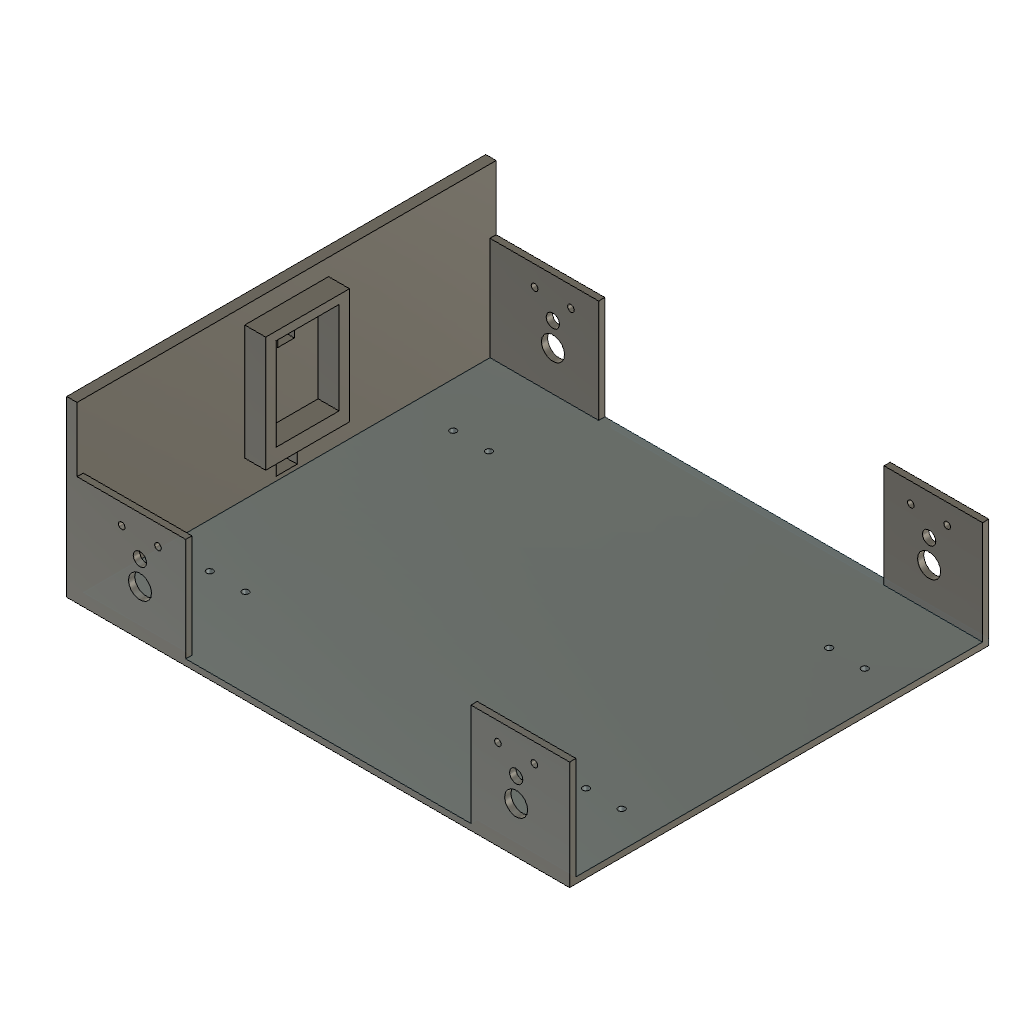
MAIN CHASSIS (Autodesk Fusion 360 design; units mm, degrees)
part number: 2026-11-04-09-08-16-697
Autodesk Fusion 360 part; units mm, degrees
derive "DerivedContext1"
sketch "Sketch1" plane through (0, 0, 0) normal (0, 0, 1) x (1, 0, 0)
  line L0 (90, 130) -> (-90, 130)
  line L1 (-90, 130) -> (-90, -130)
  line L2 (-90, -130) -> (90, -130)
  line L3 (90, -130) -> (90, 130)
  line L4 (90, 130) -> (-90, -130) construction
  line L5 (-90, 130) -> (90, -130) construction
  dimension "d1" = 260
  dimension "d2" = 180
  constraint horizontal L0
  constraint perpendicular L0 L1
  constraint parallel L0 L2
  constraint parallel L1 L3
  constraint coincident L4 origin
  constraint coincident L5 origin
  measures "d1" distance of L0.end L1.end
  measures "d2" distance of L1.end L2.end
extrude "Extrude1" add sketch "Sketch1" along normal blind 3 makes body 1
sketch "Sketch2" plane through (0, 130, 0) normal (0, 1, 0) x (-1, 0, 0)
  line L0 (90, 0) -> (90, 3)
  line L1 (-90, 3) -> (-90, 0)
  line L2 (-90, 0) -> (-90, 3)
  line L3 (90, -0.0888) -> (90, 0)
  constraint vertical L2
  constraint vertical L3
  constraint coincident L1.start L2.end
  constraint coincident L0.start L3.end
sketch "Sketch3" plane through (0, 130, 0) normal (0, 1, 0) x (-1, 0, 0)
  line L0 (250, -50) -> (30, -50)
  line L1 (30, -50) -> (30, -47)
  line L2 (30, -47) -> (250, -47)
  line L3 (250, -47) -> (250, -50)
  dimension "d5" = 220
  dimension "d6" = 3
  constraint horizontal L0
  constraint vertical L1
  constraint horizontal L2
  constraint vertical L3
  measures "d5" distance of L1.end L2.end
  measures "d6" distance of L0.end L1.end
extrude "Extrude2" add sketch "Sketch3" along normal blind 20 separate body makes body 2
combine "Combine1" operation add target body 1 tool bodies 2 makes body 3 at (-176.6667, 136.6667, -50)
move_body "Move1" bodies 3 to x (1, 0, 0) y (0, 1, 0) z (0, 0, 1) at (161.0055, -0.0826, 50.4305)
extrude "Extrude3" cut 1 faces at (131.0055, 136.5841, 1.4305) along direction (-1, 0, 0) blind 40 on bodies 3 bodies 3
extrude "Extrude4" add 1 faces at (-88.9945, 136.5841, 2.4305) along direction (-1, 0, 0) blind 20 on bodies 3 bodies 1 3
extrude "Extrude5" add 1 faces at (91.0055, 136.5841, 1.4305) along direction (1, 0, 0) blind 20 on bodies 1 bodies 1
extrude "Extrude6" add 1 faces at (30.6703, 143.2783, 0.4305) along direction (0, 0, -1) blind 0.4 on bodies 1 bodies 1
extrude "Extrude7" cut 1 faces at (-35.6612, 136.5841, 3.4305) along direction (0, 0, -1) blind 0.4 on bodies 1 bodies 1
extrude "Extrude8" add 1 faces at (-108.9945, 136.5841, 2.0305) along direction (-1, 0, 0) blind 1 on bodies 1 bodies 1
extrude "Extrude9" cut 1 faces at (111.0055, 136.5841, 2.0305) along direction (-1, 0, 0) blind 1 on bodies 1 bodies 1
sketch "Sketch4" plane through (0, 0, 3) normal (0, 0, 1) x (-1, 0, 0)
  line L0 (-90, -129.9174) -> (90, -129.9174)
  line L1 (90, -129.9174) -> (90, 130)
  line L2 (90, 130) -> (-90, 130)
  line L3 (-90, 130) -> (-90, -129.9174)
  line L4 (110, 130) -> (-110, 130)
  line L5 (-110, 130) -> (-110, 150)
  line L6 (-110, 150) -> (110, 150)
  line L7 (110, 150) -> (110, 130)
  constraint horizontal L4
  constraint vertical L5
  constraint horizontal L6
  constraint vertical L7
extrude "Extrude10" add sketch "Sketch4" along normal blind 3 separate body contours L2 L4 L5 L6 L7 makes body 4
extrude "Extrude11" add 1 faces at (30, -143.3333, 3) along direction (0, 0, -1) blind 3 on bodies 4 bodies 1 4
extrude "Extrude12" cut 1 faces at (36.6667, -143.3333, 6) along direction (0, 0, -1) blind 3 on bodies 1 bodies 1
extrude "Extrude13" add 1 faces at (30.0037, 143.2783, 0.0305) along direction (0, 0, -1) blind 0.031 on bodies 1 bodies 1
sketch "Sketch5" plane through (0, 0, 3) normal (0, 0, 1) x (-1, 0, 0)
  line L0 (-110, 150) -> (-110, 130)
  line L1 (-110, 130) -> (-90, 130)
  line L2 (-90, 130) -> (-90, -129.9174)
  line L3 (-90, -129.9174) -> (90, -129.9174)
  line L4 (90, -129.9174) -> (90, 130)
  line L5 (110, 130) -> (110, 150)
  line L6 (110, 150) -> (-110, 150)
  line L7 (90, 130) -> (110, 130)
extrude "Extrude14" add 1 faces at (110.0055, 143.2507, 1.0099) along direction (1, 0, 0) blind 20 on bodies 1 bodies 1
sketch "Sketch6" plane through (130.0055, 0, 0) normal (1, 0, 0) x (0, 1, 0)
  line L0 (149.9174, 3.0305) -> (129.9174, 3.0305)
  line L1 (129.9174, 3.0305) -> (129.9174, -0.0005)
  line L2 (129.9174, -0.0005) -> (149.9174, -0.0005)
  line L3 (149.9174, -0.0005) -> (149.9174, 3.0305)
sketch "Sketch7" plane through (0, 129.9174, 0) normal (0, -1, 0) x (1, 0, 0)
  line L0 (130.0055, 3.0305) -> (-109.9945, 3.0305)
  line L1 (-109.9945, 3.0305) -> (-109.9945, -0.0005)
  line L2 (-109.9945, -0.0005) -> (-90, -0.0005)
  line L3 (-90, -0.0005) -> (-90, 0)
  line L4 (-90, 0) -> (-90, 3)
  line L5 (-90, 3) -> (90, 3)
  line L6 (90, 3) -> (90, 0)
  line L7 (90, 0) -> (90, -0.0005)
  line L8 (90, -0.0005) -> (130.0055, -0.0005)
  line L9 (130.0055, -0.0005) -> (130.0055, 3.0305)
extrude "Extrude15" add sketch "Sketch6" along normal blind 20 bodies 1
extrude "Extrude16" add 1 faces at (-23.3278, 149.9174, 2.0202) along direction (0, 1, 0) blind 20 on bodies 1 bodies 1
extrude "Extrude17" add 1 faces at (-109.9945, 156.5841, 1.0099) along direction (-1, 0, 0) blind 40 on bodies 1 bodies 1
extrude "Extrude18" add 1 faces at (36.6667, -150, 1) along direction (0, -1, 0) blind 20 on bodies 1 bodies 1
extrude "Extrude19" add 1 faces at (-110, -156.6667, 1) along direction (-1, 0, 0) blind 40 on bodies 1 bodies 1
extrude "Extrude20" add 1 faces at (110, -156.6667, 1) along direction (1, 0, 0) blind 40 on bodies 1 bodies 1
sketch "Sketch8" plane through (0, 0, 3) normal (0, 0, 1) x (-1, 0, 0)
  line L0 (-90, -129.9174) -> (90, -129.9174)
  line L1 (90, -129.9174) -> (90, 130)
  line L2 (90, 130) -> (150, 130)
  line L3 (150, 130) -> (150, 170)
  line L4 (150, 170) -> (-150, 170)
  line L5 (-150, 170) -> (-150, 130)
  line L6 (-150, 130) -> (-90, 130)
  line L7 (-90, 130) -> (-90, -129.9174)
extrude "Extrude21" cut 1 faces at (90, -43.3609, 1) along direction (-1, 0, 0) blind 10 on bodies 1 bodies 1
extrude "Extrude22" cut 1 faces at (150.0055, 143.2507, 1.0099) along direction (-1, 0, 0) blind 10 on bodies 1 bodies 1
extrude "Extrude23" cut 1 faces at (-90, 43.2783, 1) along direction (1, 0, 0) blind 10 on bodies 1 bodies 1
extrude "Extrude24" cut 1 faces at (-149.9945, 156.5841, 1.0099) along direction (1, 0, 0) blind 10 on bodies 1 bodies 1
extrude "Extrude25" cut 1 faces at (-150, -156.6667, 1) along direction (1, 0, 0) blind 10 on bodies 1 bodies 1
extrude "Extrude26" cut 1 faces at (150, -156.6667, 1) along direction (-1, 0, 0) blind 10 on bodies 1 bodies 1
extrude "Extrude27" add 2 faces at (-120, -130, 1) (100, -130, 2) along direction (0, 1, 0) blind 20 on bodies 1 bodies 1
extrude "Extrude28" cut 1 faces at (46.6667, -170, 2) along direction (0, 1, 0) blind 20 on bodies 1 bodies 1
sketch "Sketch9" plane through (0, 0, 3) normal (0, 0, 1) x (-1, 0, 0)
  line L0 (140, 150) -> (-140, 150)
  line L1 (-140, 150) -> (-140, 110)
  line L2 (-140, 110) -> (-80, 110)
  line L3 (-80, 110) -> (-80, -129.9174)
  line L4 (-80, -129.9174) -> (80, -129.9174)
  line L5 (80, -129.9174) -> (80, 110)
  line L6 (80, 110) -> (140, 110)
  line L7 (140, 110) -> (140, 150)
extrude "Extrude29" add 2 faces at (-120, -110, 1) (100, -110, 2) along direction (0, 1, 0) blind 80 on bodies 1 bodies 1
extrude "Extrude30" cut 1 faces at (46.6667, -150, 2) along direction (0, 1, 0) blind 80 on bodies 1 bodies 1
sketch "Sketch10" plane through (0, 0, 3) normal (0, 0, 1) x (-1, 0, 0)
  line L0 (140, 70) -> (-140, 70)
  line L1 (-140, 70) -> (-140, 30)
  line L2 (-140, 30) -> (-80, 30)
  line L3 (-80, 30) -> (-80, -129.9174)
  line L4 (-80, -129.9174) -> (80, -129.9174)
  line L5 (80, -129.9174) -> (80, 30)
  line L6 (80, 30) -> (140, 30)
  line L7 (140, 30) -> (140, 70)
extrude "Extrude31" add 2 faces at (-120, -30, 1) (100, -30, 2) along direction (0, 1, 0) blind 40 on bodies 1 bodies 1
extrude "Extrude32" cut 1 faces at (46.6667, -70, 2) along direction (0, 1, 0) blind 40 on bodies 1 bodies 1
extrude "Extrude33" cut 1 faces at (-139.9945, 156.5841, 1.0099) along direction (1, 0, 0) blind 20 on bodies 1 bodies 1
extrude "Extrude34" cut 1 faces at (-80, 89.9449, 1) along direction (1, 0, 0) blind 20 on bodies 1 bodies 1
extrude "Extrude35" cut 1 faces at (-140, -3.3333, 2) along direction (1, 0, 0) blind 20 on bodies 1 bodies 1
extrude "Extrude36" cut 1 faces at (140.0055, 143.2507, 1.0099) along direction (-1, 0, 0) blind 20 on bodies 1 bodies 1
extrude "Extrude37" cut 1 faces at (140, -3.3333, 2) along direction (-1, 0, 0) blind 20 on bodies 1 bodies 1
extrude "Extrude38" cut 1 faces at (80, 49.9725, 1) along direction (-1, 0, 0) blind 20 on bodies 1 bodies 1
extrude "Extrude39" add 1 faces at (-89.9982, 129.9174, 2.0102) along direction (0, -1, 0) blind 10 on bodies 1 bodies 1
extrude "Extrude40" add 1 faces at (80, 10, 2) along direction (0, 1, 0) blind 10 on bodies 1 bodies 1
extrude "Extrude41" add 1 faces at (-100, 10, 1) along direction (0, 1, 0) blind 10 on bodies 1 bodies 1
extrude "Extrude42" add 2 faces at (-100, 20, 1) (80, 20, 2) along direction (0, 1, 0) blind 20 on bodies 1 bodies 1
extrude "Extrude43" add 1 faces at (-89.9982, 119.9174, 2.0102) along direction (0, -1, 0) blind 20 on bodies 1 bodies 1
extrude "Extrude44" cut 1 faces at (40.0055, 123.2507, 3.0305) along direction (0, 0, -1) blind 10 on bodies 1 bodies 1
extrude "Extrude45" add 1 faces at (-20, 99.9174, 2) along direction (0, 1, 0) blind 70 on bodies 1 bodies 1
extrude "Extrude46" add 1 faces at (60, 126.6116, 1) along direction (1, 0, 0) blind 60 on bodies 1 bodies 1
extrude "Extrude47" add 1 faces at (-100, 40, 1) along direction (0, 1, 0) blind 130 on bodies 1 bodies 1
sketch "Sketch11" plane through (0, 0, 3) normal (0, 0, 1) x (-1, 0, 0)
  line L0 (60, -169.9174) -> (60, -170)
  line L1 (60, -170) -> (120, -170)
  line L2 (120, -170) -> (120, 30)
  line L3 (120, 30) -> (-120, 30)
  line L4 (-120, 30) -> (-120, -169.9174)
  line L5 (-120, -169.9174) -> (60, -169.9174)
  line L6 (120, 30) -> (105, 30)
  line L7 (105, 30) -> (105, -170)
  line L8 (105, -170) -> (120, -170)
  line L9 (120, -170) -> (120, 30)
  dimension "d105" = 15
  constraint horizontal L6
  constraint vertical L7
  constraint horizontal L8
  constraint vertical L9
  constraint coincident L1 L7.end
  constraint coincident L2.end L3.start
  measures "d105" distance of L7.end L1.end
extrude "Extrude48" add sketch "Sketch11" along normal blind 70 contours L1 L2 L3 L6 L7 L8 L9 bodies 1
extrude "Extrude49" add 1 faces at (-110, 36.6667, 73) along direction (0, 0, 1) blind 10 on bodies 1 bodies 1
sketch "Sketch12" plane through (-105, 0, 0) normal (1, 0, 0) x (0, 1, 0)
  line L0 (-30, 3) -> (170, 3)
  line L1 (170, 3) -> (170, 83)
  line L2 (170, 83) -> (-30, 83)
  line L3 (-30, 83) -> (-30, 3)
  line L4 (55, 75) -> (85, 75)
  line L5 (85, 75) -> (85, 31)
  line L6 (85, 31) -> (55, 31)
  line L7 (55, 31) -> (55, 75)
  dimension "d110" = 30
  dimension "d111" = 44
  constraint horizontal L4
  constraint vertical L5
  constraint horizontal L6
  constraint vertical L7
  measures "d110" distance of L4.start L4.end
  measures "d111" distance of L4.start L6.end
extrude "Extrude50" cut sketch "Sketch12" against normal blind 10 contours L4 L5 L6 L7 bodies 1
sketch "Sketch13" plane through (-115, 0, 0) normal (1, 0, 0) x (0, 1, 0)
  line L0 (55, 31) -> (85, 31)
  line L1 (85, 31) -> (85, 75)
  line L2 (85, 75) -> (55, 75)
  line L3 (55, 75) -> (55, 31)
  line L4 (65.7, 65.8) -> (73.7, 65.8)
  line L5 (73.7, 65.8) -> (73.7, 57.8)
  line L6 (73.7, 57.8) -> (65.7, 57.8)
  line L7 (65.7, 57.8) -> (65.7, 65.8)
  dimension "d116" = 8
  dimension "d117" = 8
  constraint horizontal L4
  constraint vertical L5
  constraint horizontal L6
  constraint vertical L7
  measures "d116" distance of L5.end L6.end
  measures "d117" distance of L4.end L5.end
extrude "Extrude51" cut sketch "Sketch13" against normal blind 5 contours L4 L5 L6 L7 bodies 1
extrude "Extrude52" cut 1 faces at (-108.3333, 75, 31) along direction (0, 0, -1) blind 4 on bodies 1 bodies 1
extrude "Extrude53" add 1 faces at (-108.3333, 65, 75) along direction (0, 0, -1) blind 4 on bodies 1 bodies 1
sketch "sketch 4915" plane through (-105, 0, 0) normal (1, 0, 0) x (0, 1, 0)
  line L0 (55, 27) -> (55, 71)
  line L1 (55, 71) -> (85, 71)
  line L2 (85, 71) -> (85, 27)
  line L3 (85, 27) -> (55, 27)
  line L4 (-30, 83) -> (50, 83)
  line L5 (50, 83) -> (50, 3)
  line L6 (50, 3) -> (-30, 3)
  line L7 (-30, 3) -> (-30, 83)
  line L8 (90, 83) -> (170, 83)
  line L9 (170, 83) -> (170, 3)
  line L10 (170, 3) -> (90, 3)
  line L11 (90, 3) -> (90, 83)
  line L12 (50, 83) -> (90, 83)
  line L13 (90, 83) -> (90, 75)
  line L14 (90, 75) -> (50, 75)
  line L15 (50, 75) -> (50, 83)
  line L16 (50, 20) -> (90, 20)
  line L17 (90, 20) -> (90, 3)
  line L18 (90, 3) -> (50, 3)
  line L19 (50, 3) -> (50, 20)
  line L20 (50, 75) -> (50, 20)
  line L21 (50, 20) -> (90, 20)
  line L22 (90, 20) -> (90, 75)
  line L23 (90, 75) -> (50, 75)
extrude "Extrude54" cut sketch "sketch 4915" against normal blind 10 contours L4 L5 L6 L7 L15 L19 L20 | L5 L11 L12 L13 L14 L15 L23 | L8 L9 L10 L11 L13 L17 L22 | L5 L11 L16 L17 L18 L19 L21 bodies 1
sketch "Sketch14" plane through (-115, 0, 0) normal (1, 0, 0) x (0, 1, 0)
  line L0 (90, 20) -> (50, 20)
  line L1 (50, 20) -> (50, 75)
  line L2 (50, 75) -> (90, 75)
  line L3 (90, 75) -> (90, 20)
  line L4 (-30, 3) -> (170, 3)
  line L5 (170, 3) -> (170, 83)
  line L6 (170, 83) -> (-30, 83)
  line L7 (-30, 83) -> (-30, 3)
  line L8 (-30, 83) -> (-27, 83)
  line L9 (-27, 83) -> (-27, 3)
  line L10 (-27, 3) -> (-30, 3)
  line L11 (-30, 3) -> (-30, 83)
  dimension "d126" = 3
  constraint horizontal L8
  constraint vertical L9
  constraint horizontal L10
  constraint vertical L11
  constraint coincident L6.end L7.start
  measures "d126" distance of L6.end L8.end
extrude "Extrude55" add sketch "Sketch14" along normal blind 235 contours L4 L6 L7 L8 L9 L10 L11 bodies 1
sketch "Sketch15" plane through (-115, 0, 0) normal (1, 0, 0) x (0, 1, 0)
  line L0 (-27, 83) -> (-27, 3)
  line L1 (-27, 3) -> (170, 3)
  line L2 (170, 3) -> (170, 83)
  line L3 (170, 83) -> (-27, 83)
  line L4 (90, 20) -> (50, 20)
  line L5 (50, 20) -> (50, 75)
  line L6 (50, 75) -> (90, 75)
  line L7 (90, 75) -> (90, 20)
  line L8 (170, 83) -> (167, 83)
  line L9 (167, 83) -> (167, 3)
  line L10 (167, 3) -> (170, 3)
  line L11 (170, 3) -> (170, 83)
  dimension "d129" = 3
  constraint horizontal L8
  constraint vertical L9
  constraint horizontal L10
  constraint vertical L11
  constraint coincident L2.end L3.start
  measures "d129" distance of L2.end L8.end
extrude "Extrude56" add sketch "Sketch15" along normal blind 235 contours L1 L2 L3 L8 L9 L10 L11 bodies 1
sketch "Sketch16" plane through (0, 169.9174, 0) normal (0, 1, 0) x (-1, 0, 0)
  line L0 (-120, 0) -> (60, 0)
  line L1 (60, 0) -> (60, 3)
  line L2 (60, 3) -> (-120, 3)
  line L3 (-120, 3) -> (-120, 0)
sketch "Sketch17" plane through (0, -27, 0) normal (0, 1, 0) x (-1, 0, 0)
  line L0 (115, 3) -> (115, 83)
  line L1 (115, 83) -> (-120, 83)
  line L2 (-120, 83) -> (-120, 3)
  line L3 (-120, 3) -> (115, 3)
  line L4 (-120, 83) -> (-117, 83)
  line L5 (-117, 83) -> (-117, 3)
  line L6 (-117, 3) -> (-120, 3)
  line L7 (-120, 3) -> (-120, 83)
  dimension "d132" = 3
  constraint horizontal L4
  constraint vertical L5
  constraint horizontal L6
  constraint vertical L7
  constraint coincident L1.end L2.start
  measures "d132" distance of L1.end L4.end
extrude "Extrude57" add sketch "Sketch17" along normal blind 194 contours L1 L2 L3 L4 L5 L6 L7 bodies 1
sketch "Sketch18" plane through (-120, 0, 0) normal (-1, 0, 0) x (0, -1, 0)
  line L0 (-73.7, 57.8) -> (-73.7, 65.8)
  line L1 (-73.7, 65.8) -> (-65.7, 65.8)
  line L2 (-65.7, 65.8) -> (-65.7, 57.8)
  line L3 (-65.7, 57.8) -> (-73.7, 57.8)
  line L4 (30, 0) -> (30, 83)
  line L5 (30, 83) -> (-170, 83)
  line L6 (-170, 83) -> (-170, 0)
  line L7 (-170, 0) -> (30, 0)
  line L8 (-92, 50) -> (-47, 50)
  line L9 (-47, 50) -> (-47, 24)
  line L10 (-47, 24) -> (-92, 24)
  line L11 (-92, 24) -> (-92, 50)
  dimension "d135" = 45
  dimension "d136" = 26
  constraint horizontal L8
  constraint vertical L9
  constraint horizontal L10
  constraint vertical L11
  measures "d135" distance of L8.start L8.end
  measures "d136" distance of L8.start L10.end
extrude "Extrude58" add sketch "Sketch18" along normal blind 15 contours L8 L9 L10 L11 bodies 1
sketch "Sketch19" plane through (-135, 0, 0) normal (-1, 0, 0) x (0, -1, 0)
  line L0 (-92, 24) -> (-47, 24)
  line L1 (-47, 24) -> (-47, 50)
  line L2 (-47, 50) -> (-92, 50)
  line L3 (-92, 50) -> (-92, 24)
  line L4 (-91, 49) -> (-48, 49)
  line L5 (-48, 49) -> (-48, 25)
  line L6 (-48, 25) -> (-91, 25)
  line L7 (-91, 25) -> (-91, 49)
  constraint horizontal L4
  constraint vertical L5
  constraint horizontal L6
  constraint vertical L7
extrude "Extrude59" cut sketch "Sketch19" against normal blind 14 contours L4 L5 L6 L7 bodies 1
extrude "Extrude60" add 1 faces at (-130, 77, 50) along direction (0, 0, 1) blind 1 on bodies 1 bodies 1
extrude "Extrude61" add 1 faces at (-125, 47, 33) along direction (0, -1, 0) blind 1 on bodies 1 bodies 1
extrude "Extrude62" add 1 faces at (-125, 92, 33) along direction (0, 1, 0) blind 1 on bodies 1 bodies 1
extrude "Extrude63" add 1 faces at (-125, 77.3333, 24) along direction (0, 0, -1) blind 1 on bodies 1 bodies 1
sketch "Sketch20" plane through (0, 91, 0) normal (0, -1, 0) x (1, 0, 0)
  line L0 (-135, 49) -> (-135, 25)
  line L1 (-135, 25) -> (-121, 25)
  line L2 (-121, 25) -> (-121, 49)
  line L3 (-121, 49) -> (-135, 49)
extrude "Extrude64" add 1 faces at (-125, 93, 41.6667) along direction (0, 1, 0) blind 2 on bodies 1 bodies 1
extrude "Extrude65" cut sketch "Sketch20" against normal blind 2 bodies 1
extrude "Extrude66" add 1 faces at (-125, 46, 41.6667) along direction (0, -1, 0) blind 2 on bodies 1 bodies 1
extrude "Extrude67" cut 1 faces at (-130.3333, 48, 41) along direction (0, -1, 0) blind 2 on bodies 1 bodies 1
extrude "Extrude68" add 1 faces at (-130, 61, 23) along direction (0, 0, -1) blind 2 on bodies 1 bodies 1
extrude "Extrude69" cut 1 faces at (-130.3333, 77.3333, 25) along direction (0, 0, -1) blind 2 on bodies 1 bodies 1
sketch "Sketch21" plane through (0, 0, 21) normal (0, 0, -1) x (1, 0, 0)
  line L0 (-120, -95) -> (-120, -44)
  line L1 (-120, -44) -> (-135, -44)
  line L2 (-135, -44) -> (-135, -95)
  line L3 (-135, -95) -> (-120, -95)
  line L4 (-122.042, -59.953) -> (-132.7538, -59.953)
  line L5 (-132.7538, -59.953) -> (-132.7538, -78.5078)
  line L6 (-132.7538, -78.5078) -> (-122.042, -78.5078)
  line L7 (-122.042, -78.5078) -> (-122.042, -59.953)
  constraint horizontal L4
  constraint vertical L5
  constraint horizontal L6
  constraint vertical L7
extrude "Extrude70" cut sketch "Sketch21" against normal blind 2 contours L4 L5 L6 L7 bodies 1
sketch "Sketch22" plane through (-120, 0, 0) normal (-1, 0, 0) x (0, -1, 0)
  line L0 (-95, 21) -> (-95, 51)
  line L1 (-95, 51) -> (-44, 51)
  line L2 (-44, 51) -> (-44, 21)
  line L3 (-44, 21) -> (-95, 21)
  line L4 (-73.7, 57.8) -> (-73.7, 65.8)
  line L5 (-73.7, 65.8) -> (-65.7, 65.8)
  line L6 (-65.7, 65.8) -> (-65.7, 57.8)
  line L7 (-65.7, 57.8) -> (-73.7, 57.8)
  line L8 (30, 0) -> (30, 83)
  line L9 (30, 83) -> (-170, 83)
  line L10 (-170, 83) -> (-170, 0)
  line L11 (-170, 0) -> (30, 0)
  line L12 (-75, 5) -> (-65, 5)
  line L13 (-65, 5) -> (-65, 10)
  line L14 (-65, 10) -> (-75, 10)
  line L15 (-75, 10) -> (-75, 5)
  constraint horizontal L12
  constraint vertical L13
  constraint horizontal L14
  constraint vertical L15
extrude "Extrude71" cut sketch "Sketch22" against normal blind 5 contours L12 L13 L14 L15 bodies 1
sketch "Sketch23" plane through (0, -30, 0) normal (0, -1, 0) x (1, 0, 0)
  line L0 (120, 0) -> (120, 83)
  line L1 (120, 83) -> (-120, 83)
  line L2 (-120, 83) -> (-120, 0)
  line L3 (-120, 0) -> (120, 0)
  circle A0 centre (-84.9709, 21.9324) radius 5.5
  circle A1 centre (-85, 33.3) radius 3.15
  dimension "d166" = 11
  dimension "d168" = 6.3
  measures "d166" diameter of A0
  measures "d168" diameter of A1
extrude "Extrude72" cut sketch "Sketch23" against normal blind 3 contours A0 | A1 bodies 1
sketch "Sketch24" plane through (0, -30, 0) normal (0, -1, 0) x (1, 0, 0)
  circle A0 centre (-85, 33.3) radius 3.15
  circle A1 centre (-84.9709, 21.9324) radius 5.5
  line L0 (120, 0) -> (120, 83)
  line L1 (120, 83) -> (-120, 83)
  line L2 (-120, 83) -> (-120, 0)
  line L3 (-120, 0) -> (120, 0)
  circle A2 centre (94.4838, 22) radius 5.5
  circle A3 centre (94.4995, 33.3368) radius 3.15
  dimension "d171" = 11
  dimension "d174" = 6.3
  measures "d171" diameter of A2
  measures "d174" diameter of A3
extrude "Extrude73" cut sketch "Sketch24" against normal blind 3 contours A2 | A3 bodies 1
sketch "Sketch25" plane through (0, -30, 0) normal (0, -1, 0) x (1, 0, 0)
  circle A0 centre (94.4995, 33.3368) radius 3.15
  circle A1 centre (94.4838, 22) radius 5.5
  circle A2 centre (-85, 33.3) radius 3.15
  circle A3 centre (-84.9709, 21.9324) radius 5.5
  line L0 (120, 0) -> (120, 83)
  line L1 (120, 83) -> (-120, 83)
  line L2 (-120, 83) -> (-120, 0)
  line L3 (-120, 0) -> (120, 0)
  circle A4 centre (103.151, 42.7931) radius 1.575
  circle A5 centre (85.7765, 42.9111) radius 1.575
  line L4 (85.7765, 42.9111) -> (86.2872, 42.6287)
  dimension "d179" = 3.15
  dimension "d181" = 3.15
  constraint coincident A5.centre L4.start
  measures "d179" diameter of A4
  measures "d181" diameter of A5
extrude "Extrude74" cut sketch "Sketch25" against normal blind 3 contours A4 | A5 bodies 1
sketch "Sketch26" plane through (0, -30, 0) normal (0, -1, 0) x (1, 0, 0)
  circle A0 centre (85.7765, 42.9111) radius 1.575
  circle A1 centre (103.151, 42.7931) radius 1.575
  circle A2 centre (94.4995, 33.3368) radius 3.15
  circle A3 centre (94.4838, 22) radius 5.5
  circle A4 centre (-85, 33.3) radius 3.15
  circle A5 centre (-84.9709, 21.9324) radius 5.5
  line L0 (120, 0) -> (120, 83)
  line L1 (120, 83) -> (-120, 83)
  line L2 (-120, 83) -> (-120, 0)
  line L3 (-120, 0) -> (120, 0)
  circle A6 centre (-76.3782, 42.7246) radius 1.575
  circle A7 centre (-93.6909, 42.7533) radius 1.575
  dimension "d186" = 3.15
  dimension "d188" = 3.15
  measures "d186" diameter of A6
  measures "d188" diameter of A7
extrude "Extrude75" cut sketch "Sketch26" against normal blind 3 contours A6 | A7 bodies 1
mirror "Mirror2" about plane through (1, 70, 43) normal (0, 1, 0) of "Extrude75"
mirror "Mirror3" about plane through (1, 70, 43) normal (0, 1, 0) of "Extrude74"
mirror "Mirror4" about plane through (1, 70, 43) normal (0, 1, 0) of "Extrude73"
mirror "Mirror5" about plane through (1, 70, 43) normal (0, 1, 0) of "Extrude72"
sketch "Sketch27" plane through (0, -30, 0) normal (0, -1, 0) x (1, 0, 0)
  line L0 (120, 0) -> (120, 83)
  line L1 (120, 83) -> (-120, 83)
  line L2 (-120, 83) -> (-120, 0)
  line L3 (-120, 0) -> (120, 0)
  circle A0 centre (-84.9709, 21.9324) radius 5.5
  circle A1 centre (-85, 33.3) radius 3.15
  circle A2 centre (94.4838, 22) radius 5.5
  circle A3 centre (94.4995, 33.3368) radius 3.15
  circle A4 centre (103.151, 42.7931) radius 1.575
  circle A5 centre (85.7765, 42.9111) radius 1.575
  circle A6 centre (-76.3782, 42.7246) radius 1.575
  circle A7 centre (-93.6909, 42.7533) radius 1.575
  line L4 (-120, 83) -> (120, 83)
  line L5 (120, 83) -> (120, 52.3297)
  line L6 (120, 52.3297) -> (-120, 52.3297)
  line L7 (-120, 52.3297) -> (-120, 83)
  constraint horizontal L4
  constraint vertical L5
  constraint horizontal L6
  constraint vertical L7
  constraint coincident L0 L5.end
  constraint coincident L1.end L2.start
extrude "Extrude76" cut sketch "Sketch27" against normal blind 2 contours L0 L1 L2 L4 L5 L6 L7 bodies 1
extrude "Extrude77" cut 1 faces at (-38.3333, -28, 62.5531) along direction (0, 1, 0) blind 1 on bodies 1 bodies 1
extrude "Extrude78" add 1 faces at (-116.6667, -27, 62.5531) along direction (0, -1, 0) blind 3 on bodies 1 bodies 1
extrude "Extrude79" add 1 faces at (119, -27, 62.5531) along direction (0, -1, 0) blind 3 on bodies 1 bodies 1
sketch "Sketch28" plane through (0, -30, 0) normal (0, -1, 0) x (1, 0, 0)
  line L0 (117, 52.3297) -> (-115, 52.3297)
  line L1 (-115, 52.3297) -> (-115, 83)
  line L2 (-115, 83) -> (-120, 83)
  line L3 (-120, 83) -> (-120, 0)
  line L4 (-120, 0) -> (120, 0)
  line L5 (120, 0) -> (120, 83)
  line L6 (120, 83) -> (117, 83)
  line L7 (117, 83) -> (117, 52.3297)
  circle A0 centre (-93.6909, 42.7533) radius 1.575
  circle A1 centre (-76.3782, 42.7246) radius 1.575
  circle A2 centre (85.7765, 42.9111) radius 1.575
  circle A3 centre (103.151, 42.7931) radius 1.575
  circle A4 centre (94.4995, 33.3368) radius 3.15
  circle A5 centre (94.4838, 22) radius 5.5
  circle A6 centre (-85, 33.3) radius 3.15
  circle A7 centre (-84.9709, 21.9324) radius 5.5
  line L8 (-63.1458, 52.3297) -> (72.9075, 52.3297)
  line L9 (72.9075, 52.3297) -> (72.9075, 0)
  line L10 (72.9075, 0) -> (-63.1458, 0)
  line L11 (-63.1458, 0) -> (-63.1458, 52.3297)
  constraint horizontal L8
  constraint vertical L9
  constraint horizontal L10
  constraint vertical L11
  constraint coincident L4 L9.end
  constraint coincident L0 L8.start
extrude "Extrude80" cut sketch "Sketch28" against normal blind 3 contours L0 L4 L8 L9 L10 L11 bodies 1
extrude "Extrude81" add 1 faces at (-17.7947, -27, 2) along direction (0, -1, 0) blind 3 on bodies 1 bodies 1
mirror "Mirror6" about plane through (-89.0729, 70, 27.6648) normal (0, 1, 0) of "Extrude76"
mirror "Mirror7" about plane through (-89.0729, 70, 27.6648) normal (0, 1, 0) of "Extrude77"
mirror "Mirror8" about plane through (-89.0729, 70, 27.6648) normal (0, 1, 0) of "Extrude78"
mirror "Mirror9" about plane through (-89.0729, 70, 27.6648) normal (0, 1, 0) of "Extrude79"
mirror "Mirror10" about plane through (-89.0729, 70, 27.6648) normal (0, 1, 0) of "Extrude76"
mirror "Mirror11" about plane through (-89.0729, 70, 27.6648) normal (0, 1, 0) of "Extrude81"
mirror "Mirror12" about plane through (-89.0729, 70, 27.6648) normal (0, 1, 0) of "Extrude80"
extrude "Extrude82" add 1 faces at (-116.6667, 168, 62.5531) along direction (0, 1, 0) blind 2 on bodies 1 bodies 1
extrude "Extrude83" add 1 faces at (119, 168, 62.5531) along direction (0, 1, 0) blind 2 on bodies 1 bodies 1
extrude "Extrude84" add 1 faces at (27.5564, 167, 2) along direction (0, 1, 0) blind 3 on bodies 1 bodies 1
delete_face "DeleteFace1" 1 faces at (117, 37.6667, 19.4432) on bodies 1
sketch "Sketch29" plane through (0, -27, 0) normal (0, 1, 0) x (-1, 0, 0)
  line L0 (-120, 3) -> (-72.9075, 3)
  line L1 (-72.9075, 3) -> (-72.9075, 52.3297)
  line L2 (-72.9075, 52.3297) -> (-120, 52.3297)
  line L3 (-120, 52.3297) -> (-120, 3)
  circle A0 centre (-85.7765, 42.9111) radius 1.575
  circle A1 centre (-103.151, 42.7931) radius 1.575
  circle A2 centre (-94.4995, 33.3368) radius 3.15
  circle A3 centre (-94.4838, 22) radius 5.5
sketch "Sketch30" plane through (0, 171.7321, 0) normal (0, 1, 0) x (-1, 0, 0)
  line L0 (-108.9804, 46.2688) -> (-108.8804, 46.2688)
  arc A0 (-108.8804, 44.4379) -> (-108.8804, 46.2688) centre (-107.5987, 45.3533) ccw
  line L1 (-108.8804, 44.4379) -> (-108.9804, 44.4379)
  line L2 (-108.9804, 44.4379) -> (-108.9804, 46.2688)
  line L3 (-88.8804, 46.2211) -> (-88.8804, 44.4533)
  arc A1 (-88.8804, 46.2211) -> (-88.8804, 44.4533) centre (-90.1839, 45.3372) ccw
  line L4 (-109.8804, 5.5334) -> (-87.8804, 5.5334)
  line L5 (-87.8804, 5.5334) -> (-87.8804, 47.5334)
  line L6 (-87.8804, 47.5334) -> (-109.8804, 47.5334)
  line L7 (-109.8804, 47.5334) -> (-109.8804, 5.5334)
sketch "Sketch31" plane through (0, 0, 3) normal (0, 0, 1) x (-1, 0, 0)
  line L0 (-72.9075, 27) -> (-120, 27)
  line L1 (-120, 27) -> (-120, -167)
  line L2 (-120, -167) -> (-72.9075, -167)
  line L3 (-72.9075, -167) -> (-72.9075, -169.9174)
  line L4 (-72.9075, -169.9174) -> (-72.9075, -170)
  line L5 (-72.9075, -170) -> (63.1458, -170)
  line L6 (63.1458, -170) -> (63.1458, -167)
  line L7 (63.1458, -167) -> (115, -167)
  line L8 (115, -167) -> (115, 27)
  line L9 (115, 27) -> (63.1458, 27)
  line L10 (63.1458, 27) -> (63.1458, 30)
  line L11 (63.1458, 30) -> (-72.9075, 30)
  line L12 (-72.9075, 30) -> (-72.9075, 27)
sketch "Sketch32" plane through (0, 0, 3) normal (0, 0, 1) x (-1, 0, 0)
  circle A0 centre (-102.8136, -12.0195) radius 1.5731
  circle A1 centre (-85.81, -12.0106) radius 1.5695
extrude "Extrude85" cut sketch "Sketch32" against normal blind 3 contours A0 bodies 1
extrude "Extrude86" cut sketch "Sketch32" against normal blind 3 contours A1 bodies 1
mirror "Mirror13" about plane through (96.4537, 70, 27.6648) normal (0, 1, 0) of "Extrude86"
mirror "Mirror14" about plane through (96.4537, 70, 27.6648) normal (0, 1, 0) of "Extrude85"
extrude "Extrude87" cut 1 faces at (104.3025, -29, 52.3297) along direction (0, 0, -1) blind 0.4 on bodies 1 bodies 1
sketch "Sketch33" plane through (0, 0, 3) normal (0, 0, 1) x (-1, 0, 0)
sketch "Sketch34" plane through (0, 0, 3) normal (0, 0, 1) x (-1, 0, 0)
  circle A0 centre (76.6, -11.9333) radius 1.5538
  circle A1 centre (93.6055, -11.9234) radius 1.5469
extrude "Extrude89" cut sketch "Sketch34" against normal blind 3 contours A1 bodies 1
sketch "Sketch35" plane through (0, 0, 3) normal (0, 0, 1) x (-1, 0, 0)
  circle A0 centre (76.6037, -11.9207) radius 1.5437
extrude "Extrude90" cut sketch "Sketch35" against normal blind 3 bodies 1
mirror "Mirror15" about plane through (-89.0729, 70, 27.6648) normal (0, 1, 0) of "Extrude90"
mirror "Mirror16" about plane through (-89.0729, 70, 27.6648) normal (0, 1, 0) of "Extrude89"
